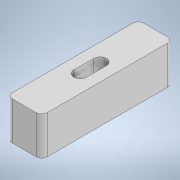
# Autodesk Inventor part: distantier_teava
Saved by Autodesk Inventor 2022.6 (Build 266554000, 554)
## iProperties
Created: 2025-11-04
Part Number: distantier_teava
Material: Generic
Document SubType Name: Modeling
Designer: Dragos Macovei
Density: 1 g/cm^3
Appearance: Default
Author: Dragos Macovei
Autodesk Inventor part; units mm, degrees
ref_plane "YZ Plane" through (0, 0, 0) normal (1, 0, 0) x (0, 1, 0)
ref_plane "XZ Plane" through (0, 0, 0) normal (0, 1, 0) x (-1, 0, 0)
ref_plane "XY Plane" through (0, 0, 0) normal (0, 0, 1) x (1, 0, 0)
sketch "Sketch1" plane through (0, 0, 0) normal (0, 1, 0) x (-1, 0, 0)
  line L0 (0, 0) -> (19, 0)
  line L1 (19, 0) -> (19, 72)
  line L2 (19, 72) -> (0, 72)
  line L3 (0, 72) -> (0, 0)
  dimension "d0" = 19
  dimension "d1" = 72
  constraints: 8 end point, 2 parallel, 1 horizontal, 1 perpendicular
  measures "d0" distance of L2.end L1.end
  measures "d1" distance of L1.end L0.end
extrude "Extrusion1" add sketch "Sketch1" along normal blind 21
sketch "Sketch2" plane through (0, 21, 0) normal (0, 1, 0) x (1, 0, 0)
  line L0 (-19, -72) -> (0, -72) projected
  line L1 (-9.5, -72) -> (-9.5, -45)
  line L2 (0, 0) -> (-19, 0) projected
  line L3 (-9.5, 0) -> (-9.5, -27)
  circle A0 centre (-9.5, -41.3547) radius 3.5
  circle A1 centre (-9.5, -30.4858) radius 3.5
  line L4 (-13, -41.3547) -> (-13, -30.4858)
  line L5 (-6, -41.3547) -> (-6, -30.4858)
  dimension "d4" = 27
  dimension "d5" = 27
  dimension "d6" = 7
  dimension "d7" = 7
  constraints: 8 end point, 4 point on circle, 3 vertical, 2 centre point, 2 midpoint, 2 tangent
  measures "d4" distance of L1.start L1.end
  measures "d5" distance of L3.start L3.end
  measures "d6" diameter of A0
  measures "d7" diameter of A1
extrude "Extrusion2" cut sketch "Sketch2" against normal blind 21
fillet "Fillet1" radius 3 4 edges at (0, 10.5, 72) (-19, 10.5, 72) (0, 10.5, 0) (-19, 10.5, 0)
body "Solid1"
